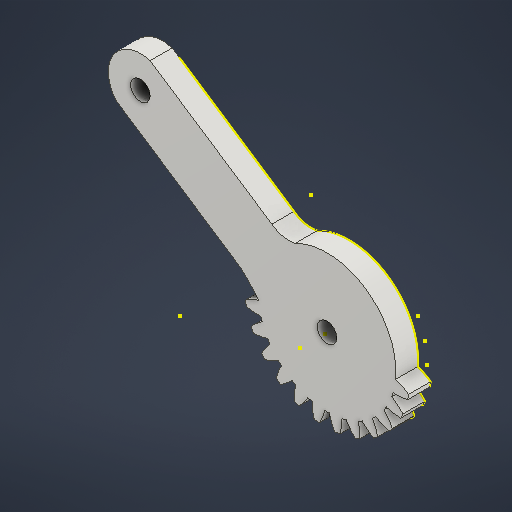
# Autodesk Inventor part: Przekładnia walcowa1
Saved by Autodesk Inventor 2026.1 (Build 301233020, 233B)
## iProperties
CustomPartVersion: 1
Created: 2026-01-25
Part Number: Przekładnia walcowa1
Material: Steel
Document SubType Name: Modeling
Designer: Nitro
Categories: <?xml version="1.0" encoding="UTF-16"?> <MemberInstance><Categories><FamilyTemplate><FamilyTemplateParameter ValueType="xs:double" Id="1" ObjectReferenceKey="da_z" ObjectType="kUserParameterObject"/><FamilyTemplateParameter ValueType="xs:double" Id="2" ObjectReferenceKey="da_b" ObjectType="kUserParameterObject"/><FamilyTemplateParameter ValueType="xs:double" Id="3" ObjectReferenceKey="da_beta" ObjectType="kUserParameterObject"/><FamilyTemplateParameter ValueType="xs:double" Id="4" ObjectReferenceKey="da_da" ObjectType="kUserParameterObject"/><FamilyTemplateParameter ValueType="xs:double" Id="5" ObjectReferenceKey="da_aw" ObjectType="kUserParameterObject"/><FamilyTemplateParameter ValueType="xs:string" Id="6" ObjectReferenceKey="EAIAABAAAACIAQAAAAAAAIAAAAAAAAAA" ObjectType="83910656" SubObjectId="SurfaceGeometry"/></FamilyTemplate><ParamToTemplateMap><ParamToTemplate CategoryParameter="//CategoryParameter[@InternalName='046C89C9-8512-4d59-83FE-43B91F4F132A']" TemplateParameter="1"/><ParamToTemplate CategoryParameter="//CategoryParameter[@InternalName='2552DF32-E462-4b46-AEBF-C6C7768E72AC']" TemplateParameter="2"/><ParamToTemplate CategoryParameter="//CategoryParameter[@InternalName='C9EE641D-15FC-4fae-A226-E94C4372FDD7']" TemplateParameter="3"/><ParamToTemplate><ParamToTemplate CategoryParameter="//CategoryParameter[@InternalName='00B6519A-459B-49c7-AD84-2E56D39A5744']" ConstantValue="0.000000"/></ParamToTemplate><ParamToTemplate><ParamToTemplate CategoryParameter="//CategoryParameter[@InternalName='04B31F0E-C7A6-4894-AA32-9629BEFACF47']" ConstantValue="1.000000"/></ParamToTemplate><ParamToTemplate><ParamToTemplate CategoryParameter="//CategoryParameter[@InternalName='43CBEC2E-7847-49e7-A936-2F7889FCB2D9']" ConstantValue="0.250000"/></ParamToTemplate><ParamToTemplate><ParamToTemplate CategoryParameter="//CategoryParameter[@InternalName='B1EFC894-105D-4ebd-86BF-FA20ED196853']" ConstantValue="0.350000"/></ParamToTemplate><ParamToTemplate><ParamToTemplate CategoryParameter="//CategoryParameter[@InternalName='51175063-3D10-4879-93E8-6246FE8B403D']" ConstantValue="2060000000.000000"/></ParamToTemplate><ParamToTemplate><ParamToTemplate CategoryParameter="//CategoryParameter[@InternalName='A3A52E27-4454-46a9-B0BD-C932399B70AF']" ConstantValue="0.300000"/></ParamToTemplate><ParamToTemplate><ParamToTemplate CategoryParameter="//CategoryParameter[@InternalName='91B76062-C214-41d9-B1B9-14D2AB99603D']" ConstantValue="0.125000"/></ParamToTemplate><ParamToTemplate><ParamToTemplate CategoryParameter="//CategoryParameter[@InternalName='374E806E-8B8A-4dda-A9AA-1039D6500AD2']" ConstantValue="8.000000"/></ParamToTemplate><ParamToTemplate><ParamToTemplate CategoryParameter="//CategoryParameter[@InternalName='2D373A89-B862-43d6-8D0B-0CBF12AB9F6C']" ConstantValue="0.349066"/></ParamToTemplate><ParamToTemplate CategoryParameter="//CategoryParameter[@InternalName='37777632-D6A2-4fac-9D53-DB8ACD95C989']" TemplateParameter="4"/><ParamToTemplate CategoryParameter="//CategoryParameter[@InternalName='FD1017F1-B727-4f7e-9707-0F86F1FF9423']" TemplateParameter="5"/><ParamToTemplate><ParamToTemplate CategoryParameter="//CategoryParameter[@InternalName='9E1B4470-B2D3-4ff1-B813-535BB4CDF51A']" ConstantValue="3520000.000000"/></ParamToTemplate><ParamToTemplate><ParamToTemplate CategoryParameter="//CategoryParameter[@InternalName='F8452263-BFF6-458c-9FB1-07C4B99E95CD']" ConstantValue="11400000.000000"/></ParamToTemplate><ParamToTemplate><ParamToTemplate CategoryParameter="//CategoryParameter[@InternalName='3E3BB259-FD49-497f-8171-6EBC954A3479']" ConstantValue="2.000000"/></ParamToTemplate><ParamToTemplate CategoryParameter="//CategoryParameter[@InternalName='27C3BAF2-7550-4e4b-AE2C-0DB134B7D9B7']" TemplateParameter="6"/></ParamToTemplateMap><Category DisplayName="Gear" InternalName="DC85795E-93AB-48d5-8EEE-5A27447B64BD" Mnemonic="Gear"><CategoryParameter DisplayName="z" InternalName="046C89C9-8512-4d59-83FE-43B91F4F132A" Mnemonic="z"/><CategoryParameter DisplayName="b" InternalName="2552DF32-E462-4b46-AEBF-C6C7768E72AC" Mnemonic="b"/><CategoryParameter DisplayName="||b|" InternalName="C9EE641D-15FC-4fae-A226-E94C4372FDD7" Mnemonic="beta"/><CategoryParameter DisplayName="x" InternalName="00B6519A-459B-49c7-AD84-2E56D39A5744" Mnemonic="x"/><CategoryParameter DisplayName="a*" InternalName="04B31F0E-C7A6-4894-AA32-9629BEFACF47" Mnemonic="a"/><CategoryParameter DisplayName="c*" InternalName="43CBEC2E-7847-49e7-A936-2F7889FCB2D9" Mnemonic="c"/><CategoryParameter DisplayName="r|.f|*" InternalName="B1EFC894-105D-4ebd-86BF-FA20ED196853" Mnemonic="rf"/><CategoryParameter DisplayName="E" InternalName="51175063-3D10-4879-93E8-6246FE8B403D" Mnemonic="E"/><CategoryParameter DisplayName="||m|" InternalName="A3A52E27-4454-46a9-B0BD-C932399B70AF" Mnemonic="mi"/><Category DisplayName="SpurGear" InternalName="26C5A22E-A91E-4dfd-A3B3-23CCAFAE1764" Mnemonic="SpurGear"><CategoryParameter DisplayName="m" InternalName="91B76062-C214-41d9-B1B9-14D2AB99603D" Mnemonic="m"/><CategoryParameter DisplayName="P" InternalName="374E806E-8B8A-4dda-A9AA-1039D6500AD2" Mnemonic="PP"/><CategoryParameter DisplayName="||a|" InternalName="2D373A89-B862-43d6-8D0B-0CBF12AB9F6C" Mnemonic="alpha"/><CategoryParameter DisplayName="d|.a|" InternalName="37777632-D6A2-4fac-9D53-DB8ACD95C989" Mnemonic="da"/><CategoryParameter DisplayName="a|.w|" InternalName="FD1017F1-B727-4f7e-9707-0F86F1FF9423" Mnemonic="aw"/><CategoryParameter DisplayName="||s||.Flim|" InternalName="9E1B4470-B2D3-4ff1-B813-535BB4CDF51A" Mnemonic="sFlim"/><CategoryParameter DisplayName="||s||.Hlim|" InternalName="F8452263-BFF6-458c-9FB1-07C4B99E95CD" Mnemonic="sHlim"/><CategoryParameter DisplayName="typ" InternalName="3E3BB259-FD49-497f-8171-6EBC954A3479" Mnemonic="type"/><CategoryParameter DisplayName="PitchDiameter" InternalName="27C3BAF2-7550-4e4b-AE2C-0DB134B7D9B7" Mnemonic="IDS_PITCHDIAM"/></Category></Category></Categories></MemberInstance>
Density: 1 g/cm^3
Appearance: Steel
Description: Zebatki chwytaka
Author: Nitro
Autodesk Inventor part; units mm, degrees
sketch "Sketch1" plane through (0, 0, 0) normal (0, 0, 1) x (1, 0, 0)
  circle A0 centre (0, 0) radius 16.875
  dimension "d0" = 33.75
  constraints: 1 centre point
  measures "d0" diameter of A0
extrude "Extrusion1" add sketch "Sketch1" along normal blind 10
ref_plane "Work Plane2" through (0, 0, 5) normal (0, 0, 1) x (1, 0, 0)
sketch "Sketch2" plane through (0, 0, 0) normal (0, 0, -1) x (-1, 0, 0)
  circle A0 centre (0, 0) radius 16.875 projected
  circle A1 centre (0, 0) radius 15.625
  dimension "d3" = 31.25
  constraints: 1 centre point, 1 coincident
  measures "d3" diameter of A1
surface extrude "Średnica podziałowa" sketch "Sketch2" against normal through all shown no curves A1
ref_plane "Work Plane8" through (0, 0, 0) normal (0.9921147, 0.1253332, 0) x (0, 0, 1)
ref_plane "Work Plane9" through (0, 0, 0) normal (1, 0, 0) x (0, 1, 0)
spur gear teeth "Przekładnia walcowa" teeth 25 pitch diameter 31.25 tip diameter 33.75 root diameter 28.125 face width 10 start plane through (0, 0, 0) normal (0, 0, -1) x (-1, 0, 0)
sketch "Szkic3" plane through (0, 0, 10) normal (0, 0, 1) x (1, 0, 0)
  point P0 (0, 0)
sketch "Szkic4" plane through (0, 0, 10) normal (0, 0, 1) x (1, 0, 0)
  circle A0 centre (0, 0) radius 14.0625
  circle A1 centre (0, 0) radius 17.8459
  line L0 (-14.0332, -0.9078) -> (-17.7928, -1.3752)
  line L1 (14.0556, -0.9078) -> (17.7928, -1.3752)
  arc A2 (-4.708, 16.205) -> (-4.7635, 13.2311) centre (6.716, 14.5042) ccw projected
  arc A3 (-4.7635, 13.2311) -> (-5.5849, 12.9059) centre (0, 0) ccw projected
  arc A4 (-5.5849, 12.9059) -> (-7.6611, 15.0357) centre (-14.8245, 5.9757) ccw projected
  arc A5 (-7.6611, 15.0357) -> (-8.5901, 14.525) centre (0, 0) ccw projected
  arc A6 (-8.5901, 14.525) -> (-7.9043, 11.6308) centre (2.8979, 15.7187) ccw projected
  arc A7 (-7.9043, 11.6308) -> (-8.619, 11.1116) centre (0, 0) ccw projected
  arc A8 (-8.619, 11.1116) -> (-11.1596, 12.6581) centre (-15.8449, 2.1013) ccw projected
  arc A9 (-11.1596, 12.6581) -> (-11.9324, 11.9324) centre (0, 0) ccw projected
  arc A10 (-11.9324, 11.9324) -> (-10.5484, 9.2997) centre (-1.1022, 15.9456) ccw projected
  arc A11 (-10.5484, 9.2997) -> (-11.1116, 8.619) centre (0, 0) ccw projected
  arc A12 (-11.1116, 8.619) -> (-13.957, 9.4852) centre (-15.8697, -1.9052) ccw projected
  arc A13 (-13.957, 9.4852) -> (-14.525, 8.5901) centre (0, 0) ccw projected
  arc A14 (-14.525, 8.5901) -> (-12.5298, 6.3842) centre (-5.0331, 15.1705) ccw projected
  arc A15 (-12.5298, 6.3842) -> (-12.9059, 5.5849) centre (0, 0) ccw projected
  arc A16 (-12.9059, 5.5849) -> (-15.8774, 5.7162) centre (-14.8973, -5.792) ccw projected
  arc A17 (-15.8774, 5.7162) -> (-16.205, 4.708) centre (0, 0) ccw projected
  arc A18 (-16.205, 4.708) -> (-13.7238, 3.0676) centre (-8.6477, 13.4422) ccw projected
  arc A19 (-13.7238, 3.0676) -> (-13.8894, 2.1999) centre (0, 0) ccw projected
  arc A20 (-13.8894, 2.1999) -> (-16.8001, 1.5881) centre (-12.9889, -9.3148) ccw projected
  arc A21 (-16.8001, 1.5881) -> (-16.8667, 0.5301) centre (0, 0) ccw projected
  arc A22 (-16.8667, 0.5301) -> (-14.0556, -0.4417) centre (-11.719, 10.8693) ccw projected
  arc A23 (-14.0556, -0.4417) -> (-14.0001, -1.3234) centre (0, 0) ccw projected
  arc A24 (-14.0001, -1.3234) -> (-16.6672, -2.6398) centre (-10.2643, -12.2524) ccw projected
  arc A25 (-16.6672, -2.6398) -> (-16.4686, -3.6812) centre (0, 0) ccw projected
  arc A26 (-16.4686, -3.6812) -> (-13.5041, -3.9233) centre (-14.0539, 7.6134) ccw projected
  arc A27 (-13.5041, -3.9233) -> (-13.2311, -4.7635) centre (0, 0) ccw projected
  arc A28 (-13.2311, -4.7635) -> (-15.4871, -6.7019) centre (-6.8948, -14.4201) ccw projected
  arc A29 (-15.4871, -6.7019) -> (-15.0357, -7.6611) centre (0, 0) ccw projected
  arc A30 (-15.0357, -7.6611) -> (-12.1042, -7.1584) centre (-15.5058, 3.8792) ccw projected
  arc A31 (-12.1042, -7.1584) -> (-11.6308, -7.9043) centre (0, 0) ccw projected
  arc A32 (-11.6308, -7.9043) -> (-13.3339, -10.3428) centre (-3.092, -15.6817) ccw projected
  arc A33 (-13.3339, -10.3428) -> (-12.6581, -11.1596) centre (0, 0) ccw projected
  arc A34 (-12.6581, -11.1596) -> (-9.9437, -9.9437) centre (-15.9833, -0.0988) ccw projected
  arc A35 (-9.9437, -9.9437) -> (-9.2997, -10.5484) centre (0, 0) ccw projected
  arc A36 (-9.2997, -10.5484) -> (-10.3428, -13.3339) centre (0.905, -15.958) ccw projected
  arc A37 (-10.3428, -13.3339) -> (-9.4852, -13.957) centre (0, 0) ccw projected
  arc A38 (-9.4852, -13.957) -> (-7.1584, -12.1042) centre (-15.4566, -4.0706) ccw projected
  arc A39 (-7.1584, -12.1042) -> (-6.3842, -12.5298) centre (0, 0) ccw projected
  arc A40 (-6.3842, -12.5298) -> (-6.7019, -15.4871) centre (4.8451, -15.2316) ccw projected
  arc A41 (-6.7019, -15.4871) -> (-5.7162, -15.8774) centre (0, 0) ccw projected
  arc A42 (-5.7162, -15.8774) -> (-3.9233, -13.5041) centre (-13.9587, -7.7866) ccw projected
  arc A43 (-3.9233, -13.5041) -> (-3.0676, -13.7238) centre (0, 0) ccw projected
  arc A44 (-3.0676, -13.7238) -> (-2.6398, -16.6672) centre (8.4809, -13.5481) ccw projected
  arc A45 (-2.6398, -16.6672) -> (-1.5881, -16.8001) centre (0, 0) ccw projected
  arc A46 (-1.5881, -16.8001) -> (-0.4417, -14.0556) centre (-11.5837, -11.0134) ccw projected
  arc A47 (-0.4417, -14.0556) -> (0.4417, -14.0556) centre (0, 0) ccw projected
  arc A48 (0.4417, -14.0556) -> (1.5881, -16.8001) centre (11.5837, -11.0134) ccw projected
  arc A49 (1.5881, -16.8001) -> (2.6398, -16.6672) centre (0, 0) ccw projected
  arc A50 (2.6398, -16.6672) -> (3.0676, -13.7238) centre (-8.4809, -13.5481) ccw projected
  arc A51 (3.0676, -13.7238) -> (3.9233, -13.5041) centre (0, 0) ccw projected
  arc A52 (3.9233, -13.5041) -> (5.7162, -15.8774) centre (13.9587, -7.7866) ccw projected
  arc A53 (5.7162, -15.8774) -> (6.7019, -15.4871) centre (0, 0) ccw projected
  arc A54 (6.7019, -15.4871) -> (6.3842, -12.5298) centre (-4.8451, -15.2316) ccw projected
  arc A55 (6.3842, -12.5298) -> (7.1584, -12.1042) centre (0, 0) ccw projected
  arc A56 (7.1584, -12.1042) -> (9.4852, -13.957) centre (15.4566, -4.0706) ccw projected
  arc A57 (9.4852, -13.957) -> (10.3428, -13.3339) centre (0, 0) ccw projected
  arc A58 (10.3428, -13.3339) -> (9.2997, -10.5484) centre (-0.905, -15.958) ccw projected
  arc A59 (9.2997, -10.5484) -> (9.9437, -9.9437) centre (0, 0) ccw projected
  arc A60 (9.9437, -9.9437) -> (12.6581, -11.1596) centre (15.9833, -0.0988) ccw projected
  arc A61 (12.6581, -11.1596) -> (13.3339, -10.3428) centre (0, 0) ccw projected
  arc A62 (13.3339, -10.3428) -> (11.6308, -7.9043) centre (3.092, -15.6817) ccw projected
  arc A63 (11.6308, -7.9043) -> (12.1042, -7.1584) centre (0, 0) ccw projected
  arc A64 (12.1042, -7.1584) -> (15.0357, -7.6611) centre (15.5058, 3.8792) ccw projected
  arc A65 (15.0357, -7.6611) -> (15.4871, -6.7019) centre (0, 0) ccw projected
  arc A66 (15.4871, -6.7019) -> (13.2311, -4.7635) centre (6.8948, -14.4201) ccw projected
  arc A67 (13.2311, -4.7635) -> (13.5041, -3.9233) centre (0, 0) ccw projected
  arc A68 (13.5041, -3.9233) -> (16.4686, -3.6812) centre (14.0539, 7.6134) ccw projected
  arc A69 (16.4686, -3.6812) -> (16.6672, -2.6398) centre (0, 0) ccw projected
  arc A70 (16.6672, -2.6398) -> (14.0001, -1.3234) centre (10.2643, -12.2524) ccw projected
  arc A71 (14.0001, -1.3234) -> (14.0556, -0.4417) centre (0, 0) ccw projected
  arc A72 (14.0556, -0.4417) -> (16.8667, 0.5301) centre (11.719, 10.8693) ccw projected
  arc A73 (16.8667, 0.5301) -> (16.8001, 1.5881) centre (0, 0) ccw projected
  arc A74 (16.8001, 1.5881) -> (13.8894, 2.1999) centre (12.9889, -9.3148) ccw projected
  arc A75 (13.8894, 2.1999) -> (13.7238, 3.0676) centre (0, 0) ccw projected
  arc A76 (13.7238, 3.0676) -> (16.205, 4.708) centre (8.6477, 13.4422) ccw projected
  arc A77 (16.205, 4.708) -> (15.8774, 5.7162) centre (0, 0) ccw projected
  arc A78 (15.8774, 5.7162) -> (12.9059, 5.5849) centre (14.8973, -5.792) ccw projected
  arc A79 (12.9059, 5.5849) -> (12.5298, 6.3842) centre (0, 0) ccw projected
  arc A80 (12.5298, 6.3842) -> (14.525, 8.5901) centre (5.0331, 15.1705) ccw projected
  arc A81 (14.525, 8.5901) -> (13.957, 9.4852) centre (0, 0) ccw projected
  arc A82 (13.957, 9.4852) -> (11.1116, 8.619) centre (15.8697, -1.9052) ccw projected
  arc A83 (11.1116, 8.619) -> (10.5484, 9.2997) centre (0, 0) ccw projected
  arc A84 (10.5484, 9.2997) -> (11.9324, 11.9324) centre (1.1022, 15.9456) ccw projected
  arc A85 (11.9324, 11.9324) -> (11.1596, 12.6581) centre (0, 0) ccw projected
  arc A86 (11.1596, 12.6581) -> (8.619, 11.1116) centre (15.8449, 2.1013) ccw projected
  arc A87 (8.619, 11.1116) -> (7.9043, 11.6308) centre (0, 0) ccw projected
  arc A88 (7.9043, 11.6308) -> (8.5901, 14.525) centre (-2.8979, 15.7187) ccw projected
  arc A89 (8.5901, 14.525) -> (7.6611, 15.0357) centre (0, 0) ccw projected
  arc A90 (7.6611, 15.0357) -> (5.5849, 12.9059) centre (14.8245, 5.9757) ccw projected
  arc A91 (5.5849, 12.9059) -> (4.7635, 13.2311) centre (0, 0) ccw projected
  arc A92 (4.7635, 13.2311) -> (4.708, 16.205) centre (-6.716, 14.5042) ccw projected
  arc A93 (4.708, 16.205) -> (3.6812, 16.4686) centre (0, 0) ccw projected
  arc A94 (3.6812, 16.4686) -> (2.1999, 13.8894) centre (12.8727, 9.4747) ccw projected
  arc A95 (2.1999, 13.8894) -> (1.3234, 14.0001) centre (0, 0) ccw projected
  arc A96 (1.3234, 14.0001) -> (0.5301, 16.8667) centre (-10.112, 12.3784) ccw projected
  arc A97 (0.5301, 16.8667) -> (-0.5301, 16.8667) centre (0, 0) ccw projected
  arc A98 (-0.5301, 16.8667) -> (-1.3234, 14.0001) centre (10.112, 12.3784) ccw projected
  arc A99 (-1.3234, 14.0001) -> (-2.1999, 13.8894) centre (0, 0) ccw projected
  arc A100 (-2.1999, 13.8894) -> (-3.6812, 16.4686) centre (-12.8727, 9.4747) ccw projected
  arc A101 (-3.6812, 16.4686) -> (-4.708, 16.205) centre (0, 0) ccw projected
  point P0 (14.0001, -1.3234)
  point P1 (13.5041, -3.9233)
  point P2 (13.2311, -4.7635)
  point P3 (12.1042, -7.1584)
  point P4 (11.6308, -7.9043)
  point P5 (9.9437, -9.9437)
  point P6 (9.2997, -10.5484)
  point P7 (7.1584, -12.1042)
  point P8 (6.3842, -12.5298)
  point P9 (3.9233, -13.5041)
  point P10 (3.0676, -13.7238)
  point P11 (0.4417, -14.0556)
  point P12 (-0.4417, -14.0556)
  point P13 (-3.0676, -13.7238)
  point P14 (-3.9233, -13.5041)
  point P15 (-6.3842, -12.5298)
  point P16 (-7.1584, -12.1042)
  point P17 (-9.2997, -10.5484)
  point P18 (-9.9437, -9.9437)
  point P19 (-11.6308, -7.9043)
  point P20 (-12.1042, -7.1584)
  point P21 (-13.2311, -4.7635)
  point P22 (-13.5041, -3.9233)
  point P23 (-14.0001, -1.3234)
  constraints: 4 end point, 2 coincident, 2 point on circle, 1 centre point, 4 other
extrude "Wyciągnięcie proste2" cut sketch "Szkic4" against normal blind 10 contours A0 A74 A73 A72 | A0 A78 A77 A76 | A0 A82 A81 A80 | A0 A86 A85 A84 | A0 A90 A89 A88 | A0 A94 A93 A92 | A0 A98 A97 A96 | A0 A2 A101 A100 | A0 A6 A5 A4 | A0 A10 A9 A8 | A0 A14 A13 A12 | A0 A18 A17 A16 | A0 A22 A21 A20 | A1
sketch "Szkic5" plane through (0, 0, 10) normal (0, 0, 1) x (1, 0, 0)
  circle A0 centre (0, 0) radius 25.2882
  constraints: 1 centre point, 1 coincident
extrude "Wyciągnięcie proste3" cut sketch "Szkic5" against normal blind 5
sketch "Szkic6" plane through (0, 0, 5) normal (0, 0, 1) x (1, 0, 0)
  point P0 (0, 0)
sketch "Szkic7" plane through (0, 0, 5) normal (0, 0, 1) x (1, 0, 0)
  point P0 (0, 0)
sketch "Szkic8" plane through (0, 0, 5) normal (0, 0, 1) x (1, 0, 0)
  arc A0 (13.2311, -4.7635) -> (13.5041, -3.9233) centre (0, 0) ccw projected
  arc A1 (13.5041, -3.9233) -> (16.4686, -3.6812) centre (14.0539, 7.6134) ccw projected
  arc A2 (16.4686, -3.6812) -> (16.6672, -2.6398) centre (0, 0) ccw projected
  arc A3 (16.6672, -2.6398) -> (14.0001, -1.3234) centre (10.2643, -12.2524) ccw projected
  arc A4 (14.0001, -1.3234) -> (-14.0001, -1.3234) centre (0, 0) ccw projected
  arc A5 (-14.0001, -1.3234) -> (-16.6672, -2.6398) centre (-10.2643, -12.2524) ccw projected
  arc A6 (-16.6672, -2.6398) -> (-16.4686, -3.6812) centre (0, 0) ccw projected
  arc A7 (-16.4686, -3.6812) -> (-13.5041, -3.9233) centre (-14.0539, 7.6134) ccw projected
  arc A8 (-13.5041, -3.9233) -> (-13.2311, -4.7635) centre (0, 0) ccw projected
  arc A9 (-13.2311, -4.7635) -> (-15.4871, -6.7019) centre (-6.8948, -14.4201) ccw projected
  arc A10 (-15.4871, -6.7019) -> (-15.0357, -7.6611) centre (0, 0) ccw projected
  arc A11 (-15.0357, -7.6611) -> (-12.1042, -7.1584) centre (-15.5058, 3.8792) ccw projected
  arc A12 (-12.1042, -7.1584) -> (-11.6308, -7.9043) centre (0, 0) ccw projected
  arc A13 (-11.6308, -7.9043) -> (-13.3339, -10.3428) centre (-3.092, -15.6817) ccw projected
  arc A14 (-13.3339, -10.3428) -> (-12.6581, -11.1596) centre (0, 0) ccw projected
  arc A15 (-12.6581, -11.1596) -> (-9.9437, -9.9437) centre (-15.9833, -0.0988) ccw projected
  arc A16 (-9.9437, -9.9437) -> (-9.2997, -10.5484) centre (0, 0) ccw projected
  arc A17 (-9.2997, -10.5484) -> (-10.3428, -13.3339) centre (0.905, -15.958) ccw projected
  arc A18 (-10.3428, -13.3339) -> (-9.4852, -13.957) centre (0, 0) ccw projected
  arc A19 (-9.4852, -13.957) -> (-7.1584, -12.1042) centre (-15.4566, -4.0706) ccw projected
  arc A20 (-7.1584, -12.1042) -> (-6.3842, -12.5298) centre (0, 0) ccw projected
  arc A21 (-6.3842, -12.5298) -> (-6.7019, -15.4871) centre (4.8451, -15.2316) ccw projected
  arc A22 (-6.7019, -15.4871) -> (-5.7162, -15.8774) centre (0, 0) ccw projected
  arc A23 (-5.7162, -15.8774) -> (-3.9233, -13.5041) centre (-13.9587, -7.7866) ccw projected
  arc A24 (-3.9233, -13.5041) -> (-3.0676, -13.7238) centre (0, 0) ccw projected
  arc A25 (-3.0676, -13.7238) -> (-2.6398, -16.6672) centre (8.4809, -13.5481) ccw projected
  arc A26 (-2.6398, -16.6672) -> (-1.5881, -16.8001) centre (0, 0) ccw projected
  arc A27 (-1.5881, -16.8001) -> (-0.4417, -14.0556) centre (-11.5837, -11.0134) ccw projected
  arc A28 (-0.4417, -14.0556) -> (0.4417, -14.0556) centre (0, 0) ccw projected
  arc A29 (0.4417, -14.0556) -> (1.5881, -16.8001) centre (11.5837, -11.0134) ccw projected
  arc A30 (1.5881, -16.8001) -> (2.6398, -16.6672) centre (0, 0) ccw projected
  arc A31 (2.6398, -16.6672) -> (3.0676, -13.7238) centre (-8.4809, -13.5481) ccw projected
  arc A32 (3.0676, -13.7238) -> (3.9233, -13.5041) centre (0, 0) ccw projected
  arc A33 (3.9233, -13.5041) -> (5.7162, -15.8774) centre (13.9587, -7.7866) ccw projected
  arc A34 (5.7162, -15.8774) -> (6.7019, -15.4871) centre (0, 0) ccw projected
  arc A35 (6.7019, -15.4871) -> (6.3842, -12.5298) centre (-4.8451, -15.2316) ccw projected
  arc A36 (6.3842, -12.5298) -> (7.1584, -12.1042) centre (0, 0) ccw projected
  arc A37 (7.1584, -12.1042) -> (9.4852, -13.957) centre (15.4566, -4.0706) ccw projected
  arc A38 (9.4852, -13.957) -> (10.3428, -13.3339) centre (0, 0) ccw projected
  arc A39 (10.3428, -13.3339) -> (9.2997, -10.5484) centre (-0.905, -15.958) ccw projected
  arc A40 (9.2997, -10.5484) -> (9.9437, -9.9437) centre (0, 0) ccw projected
  arc A41 (9.9437, -9.9437) -> (12.6581, -11.1596) centre (15.9833, -0.0988) ccw projected
  arc A42 (12.6581, -11.1596) -> (13.3339, -10.3428) centre (0, 0) ccw projected
  arc A43 (13.3339, -10.3428) -> (11.6308, -7.9043) centre (3.092, -15.6817) ccw projected
  arc A44 (11.6308, -7.9043) -> (12.1042, -7.1584) centre (0, 0) ccw projected
  arc A45 (12.1042, -7.1584) -> (15.0357, -7.6611) centre (15.5058, 3.8792) ccw projected
  arc A46 (15.0357, -7.6611) -> (15.4871, -6.7019) centre (0, 0) ccw projected
  arc A47 (15.4871, -6.7019) -> (13.2311, -4.7635) centre (6.8948, -14.4201) ccw projected
  line L0 (-8.1721, 11.4442) -> (-34.5152, 28.8945)
  line L1 (-14.0607, 0.2225) -> (-41.4775, 18.3841)
  line L2 (-5.8927, 15.7879) -> (-5.8933, 15.7868)
  arc A48 (-34.5152, 28.8945) -> (-41.4775, 18.3841) centre (-36.4521, 22.6163) ccw
  arc A49 (-11.2616, 13.4908) -> (-6.5061, 12.4669) centre (-7.7853, 18.0815) ccw
  line L3 (-10.6564, 13.0899) -> (-17.6188, 2.5795)
  arc A50 (14.0001, -1.3234) -> (-14.0001, -1.3234) centre (0, 0) ccw projected
  arc A51 (-14.0001, -1.3234) -> (-17.6188, 2.5795) centre (-34.4614, -16.666) ccw
  constraints: 11 point on circle, 8 end point, 4 point on line, 3 centre point, 2 coincident, 1 parallel, 1 perpendicular
extrude "Wyciągnięcie proste4" add sketch "Szkic8" against normal blind 5 contours A4 L0 A49 | A4 L1 L3 L0 | L3 L1 A48 L0 A49 | A4 A51 L1
sketch "Szkic9" plane through (0, 0, 5) normal (0, 0, 1) x (1, 0, 0)
  arc A0 (13.2311, -4.7635) -> (13.5041, -3.9233) centre (0, 0) ccw projected
  arc A1 (13.5041, -3.9233) -> (16.4686, -3.6812) centre (14.0539, 7.6134) ccw projected
  arc A2 (16.4686, -3.6812) -> (16.6672, -2.6398) centre (0, 0) ccw projected
  arc A3 (16.6672, -2.6398) -> (14.0001, -1.3234) centre (10.2643, -12.2524) ccw projected
  arc A4 (14.0001, -1.3234) -> (-6.5061, 12.4669) centre (0, 0) ccw projected
  arc A5 (-11.2616, 13.4908) -> (-6.5061, 12.4669) centre (-7.7853, 18.0815) ccw projected
  line L0 (-11.2616, 13.4908) -> (-34.5152, 28.8945) projected
  arc A6 (-34.5152, 28.8945) -> (-41.4775, 18.3841) centre (-36.4521, 22.6163) ccw projected
  line L1 (-41.4775, 18.3841) -> (-17.6188, 2.5795) projected
  arc A7 (-14.0001, -1.3234) -> (-17.6188, 2.5795) centre (-34.4614, -16.666) ccw projected
  arc A8 (-14.0001, -1.3234) -> (-16.6672, -2.6398) centre (-10.2643, -12.2524) ccw projected
  arc A9 (-16.6672, -2.6398) -> (-16.4686, -3.6812) centre (0, 0) ccw projected
  arc A10 (-16.4686, -3.6812) -> (-13.5041, -3.9233) centre (-14.0539, 7.6134) ccw projected
  arc A11 (-13.5041, -3.9233) -> (-13.2311, -4.7635) centre (0, 0) ccw projected
  arc A12 (-13.2311, -4.7635) -> (-15.4871, -6.7019) centre (-6.8948, -14.4201) ccw projected
  arc A13 (-15.4871, -6.7019) -> (-15.0357, -7.6611) centre (0, 0) ccw projected
  arc A14 (-15.0357, -7.6611) -> (-12.1042, -7.1584) centre (-15.5058, 3.8792) ccw projected
  arc A15 (-12.1042, -7.1584) -> (-11.6308, -7.9043) centre (0, 0) ccw projected
  arc A16 (-11.6308, -7.9043) -> (-13.3339, -10.3428) centre (-3.092, -15.6817) ccw projected
  arc A17 (-13.3339, -10.3428) -> (-12.6581, -11.1596) centre (0, 0) ccw projected
  arc A18 (-12.6581, -11.1596) -> (-9.9437, -9.9437) centre (-15.9833, -0.0988) ccw projected
  arc A19 (-9.9437, -9.9437) -> (-9.2997, -10.5484) centre (0, 0) ccw projected
  arc A20 (-9.2997, -10.5484) -> (-10.3428, -13.3339) centre (0.905, -15.958) ccw projected
  arc A21 (-10.3428, -13.3339) -> (-9.4852, -13.957) centre (0, 0) ccw projected
  arc A22 (-9.4852, -13.957) -> (-7.1584, -12.1042) centre (-15.4566, -4.0706) ccw projected
  arc A23 (-7.1584, -12.1042) -> (-6.3842, -12.5298) centre (0, 0) ccw projected
  arc A24 (-6.3842, -12.5298) -> (-6.7019, -15.4871) centre (4.8451, -15.2316) ccw projected
  arc A25 (-6.7019, -15.4871) -> (-5.7162, -15.8774) centre (0, 0) ccw projected
  arc A26 (-5.7162, -15.8774) -> (-3.9233, -13.5041) centre (-13.9587, -7.7866) ccw projected
  arc A27 (-3.9233, -13.5041) -> (-3.0676, -13.7238) centre (0, 0) ccw projected
  arc A28 (-3.0676, -13.7238) -> (-2.6398, -16.6672) centre (8.4809, -13.5481) ccw projected
  arc A29 (-2.6398, -16.6672) -> (-1.5881, -16.8001) centre (0, 0) ccw projected
  arc A30 (-1.5881, -16.8001) -> (-0.4417, -14.0556) centre (-11.5837, -11.0134) ccw projected
  arc A31 (-0.4417, -14.0556) -> (0.4417, -14.0556) centre (0, 0) ccw projected
  arc A32 (0.4417, -14.0556) -> (1.5881, -16.8001) centre (11.5837, -11.0134) ccw projected
  arc A33 (1.5881, -16.8001) -> (2.6398, -16.6672) centre (0, 0) ccw projected
  arc A34 (2.6398, -16.6672) -> (3.0676, -13.7238) centre (-8.4809, -13.5481) ccw projected
  arc A35 (3.0676, -13.7238) -> (3.9233, -13.5041) centre (0, 0) ccw projected
  arc A36 (3.9233, -13.5041) -> (5.7162, -15.8774) centre (13.9587, -7.7866) ccw projected
  arc A37 (5.7162, -15.8774) -> (6.7019, -15.4871) centre (0, 0) ccw projected
  arc A38 (6.7019, -15.4871) -> (6.3842, -12.5298) centre (-4.8451, -15.2316) ccw projected
  arc A39 (6.3842, -12.5298) -> (7.1584, -12.1042) centre (0, 0) ccw projected
  arc A40 (7.1584, -12.1042) -> (9.4852, -13.957) centre (15.4566, -4.0706) ccw projected
  arc A41 (9.4852, -13.957) -> (10.3428, -13.3339) centre (0, 0) ccw projected
  arc A42 (10.3428, -13.3339) -> (9.2997, -10.5484) centre (-0.905, -15.958) ccw projected
  arc A43 (9.2997, -10.5484) -> (9.9437, -9.9437) centre (0, 0) ccw projected
  arc A44 (9.9437, -9.9437) -> (12.6581, -11.1596) centre (15.9833, -0.0988) ccw projected
  arc A45 (12.6581, -11.1596) -> (13.3339, -10.3428) centre (0, 0) ccw projected
  arc A46 (13.3339, -10.3428) -> (11.6308, -7.9043) centre (3.092, -15.6817) ccw projected
  arc A47 (11.6308, -7.9043) -> (12.1042, -7.1584) centre (0, 0) ccw projected
  arc A48 (12.1042, -7.1584) -> (15.0357, -7.6611) centre (15.5058, 3.8792) ccw projected
  arc A49 (15.0357, -7.6611) -> (15.4871, -6.7019) centre (0, 0) ccw projected
  arc A50 (15.4871, -6.7019) -> (13.2311, -4.7635) centre (6.8948, -14.4201) ccw projected
  circle A51 centre (-36.4521, 22.6163) radius 3
  dimension "d55" = 6
  constraints: 1 centre point, 1 coincident
  measures "d55" diameter of A51
extrude "Wyciągnięcie proste5" cut sketch "Szkic9" against normal blind 5 contours A51
sketch "Szkic10" plane through (0, 0, 0) normal (0, 0, -1) x (-1, 0, 0)
  circle A0 centre (0, 0) radius 3
  dimension "d58" = 6
  constraints: 1 centre point, 1 coincident
  measures "d58" diameter of A0
extrude "Wyciągnięcie proste6" cut sketch "Szkic10" against normal blind 5
sketch "Szkic11" plane through (0, 0, 0) normal (0, 0, -1) x (-1, 0, 0)
  circle A0 centre (0, 0) radius 3 projected
  circle A1 centre (36.4521, 22.6163) radius 3 projected
  arc A2 (6.5061, 12.4669) -> (-14.0001, -1.3234) centre (0, 0) ccw projected
  arc A3 (-14.0001, -1.3234) -> (-16.6672, -2.6398) centre (-10.2643, -12.2524) ccw projected
  arc A4 (-16.6672, -2.6398) -> (-16.4686, -3.6812) centre (0, 0) ccw projected
  arc A5 (-16.4686, -3.6812) -> (-13.5041, -3.9233) centre (-14.0539, 7.6134) ccw projected
  arc A6 (-13.5041, -3.9233) -> (-13.2311, -4.7635) centre (0, 0) ccw projected
  arc A7 (-13.2311, -4.7635) -> (-15.4871, -6.7019) centre (-6.8948, -14.4201) ccw projected
  arc A8 (-15.4871, -6.7019) -> (-15.0357, -7.6611) centre (0, 0) ccw projected
  arc A9 (-15.0357, -7.6611) -> (-12.1042, -7.1584) centre (-15.5058, 3.8792) ccw projected
  arc A10 (-12.1042, -7.1584) -> (-11.6308, -7.9043) centre (0, 0) ccw projected
  arc A11 (-11.6308, -7.9043) -> (-13.3339, -10.3428) centre (-3.092, -15.6817) ccw projected
  arc A12 (-13.3339, -10.3428) -> (-12.6581, -11.1596) centre (0, 0) ccw projected
  arc A13 (-12.6581, -11.1596) -> (-9.9437, -9.9437) centre (-15.9833, -0.0988) ccw projected
  arc A14 (-9.9437, -9.9437) -> (-9.2997, -10.5484) centre (0, 0) ccw projected
  arc A15 (-9.2997, -10.5484) -> (-10.3428, -13.3339) centre (0.905, -15.958) ccw projected
  arc A16 (-10.3428, -13.3339) -> (-9.4852, -13.957) centre (0, 0) ccw projected
  arc A17 (-9.4852, -13.957) -> (-7.1584, -12.1042) centre (-15.4566, -4.0706) ccw projected
  arc A18 (-7.1584, -12.1042) -> (-6.3842, -12.5298) centre (0, 0) ccw projected
  arc A19 (-6.3842, -12.5298) -> (-6.7019, -15.4871) centre (4.8451, -15.2316) ccw projected
  arc A20 (-6.7019, -15.4871) -> (-5.7162, -15.8774) centre (0, 0) ccw projected
  arc A21 (-5.7162, -15.8774) -> (-3.9233, -13.5041) centre (-13.9587, -7.7866) ccw projected
  arc A22 (-3.9233, -13.5041) -> (-3.0676, -13.7238) centre (0, 0) ccw projected
  arc A23 (-3.0676, -13.7238) -> (-2.6398, -16.6672) centre (8.4809, -13.5481) ccw projected
  arc A24 (-2.6398, -16.6672) -> (-1.5881, -16.8001) centre (0, 0) ccw projected
  arc A25 (-1.5881, -16.8001) -> (-0.4417, -14.0556) centre (-11.5837, -11.0134) ccw projected
  arc A26 (-0.4417, -14.0556) -> (0.4417, -14.0556) centre (0, 0) ccw projected
  arc A27 (0.4417, -14.0556) -> (1.5881, -16.8001) centre (11.5837, -11.0134) ccw projected
  arc A28 (1.5881, -16.8001) -> (2.6398, -16.6672) centre (0, 0) ccw projected
  arc A29 (2.6398, -16.6672) -> (3.0676, -13.7238) centre (-8.4809, -13.5481) ccw projected
  arc A30 (3.0676, -13.7238) -> (3.9233, -13.5041) centre (0, 0) ccw projected
  arc A31 (3.9233, -13.5041) -> (5.7162, -15.8774) centre (13.9587, -7.7866) ccw projected
  arc A32 (5.7162, -15.8774) -> (6.7019, -15.4871) centre (0, 0) ccw projected
  arc A33 (6.7019, -15.4871) -> (6.3842, -12.5298) centre (-4.8451, -15.2316) ccw projected
  arc A34 (6.3842, -12.5298) -> (7.1584, -12.1042) centre (0, 0) ccw projected
  arc A35 (7.1584, -12.1042) -> (9.4852, -13.957) centre (15.4566, -4.0706) ccw projected
  arc A36 (9.4852, -13.957) -> (10.3428, -13.3339) centre (0, 0) ccw projected
  arc A37 (10.3428, -13.3339) -> (9.2997, -10.5484) centre (-0.905, -15.958) ccw projected
  arc A38 (9.2997, -10.5484) -> (9.9437, -9.9437) centre (0, 0) ccw projected
  arc A39 (9.9437, -9.9437) -> (12.6581, -11.1596) centre (15.9833, -0.0988) ccw projected
  arc A40 (12.6581, -11.1596) -> (13.3339, -10.3428) centre (0, 0) ccw projected
  arc A41 (13.3339, -10.3428) -> (11.6308, -7.9043) centre (3.092, -15.6817) ccw projected
  arc A42 (11.6308, -7.9043) -> (12.1042, -7.1584) centre (0, 0) ccw projected
  arc A43 (12.1042, -7.1584) -> (15.0357, -7.6611) centre (15.5058, 3.8792) ccw projected
  arc A44 (15.0357, -7.6611) -> (15.4871, -6.7019) centre (0, 0) ccw projected
  arc A45 (15.4871, -6.7019) -> (13.2311, -4.7635) centre (6.8948, -14.4201) ccw projected
  arc A46 (13.2311, -4.7635) -> (13.5041, -3.9233) centre (0, 0) ccw projected
  arc A47 (13.5041, -3.9233) -> (16.4686, -3.6812) centre (14.0539, 7.6134) ccw projected
  arc A48 (16.4686, -3.6812) -> (16.6672, -2.6398) centre (0, 0) ccw projected
  arc A49 (16.6672, -2.6398) -> (14.0001, -1.3234) centre (10.2643, -12.2524) ccw projected
  arc A50 (17.6188, 2.5795) -> (14.0001, -1.3234) centre (34.4614, -16.666) ccw projected
  line L0 (17.6188, 2.5795) -> (41.4775, 18.3841) projected
  arc A51 (41.4775, 18.3841) -> (34.5152, 28.8945) centre (36.4521, 22.6163) ccw projected
  line L1 (34.5152, 28.8945) -> (11.2616, 13.4908) projected
  arc A52 (6.5061, 12.4669) -> (11.2616, 13.4908) centre (7.7853, 18.0815) ccw projected
sketch "Szkic12" plane through (0, 0, 0) normal (0, 0, -1) x (-1, 0, 0)
  line L0 (34.5152, 28.8945) -> (11.2616, 13.4908) projected
  circle A0 centre (0, 0) radius 3 projected
  circle A1 centre (36.4521, 22.6163) radius 3 projected
  arc A2 (6.5061, 12.4669) -> (-14.0001, -1.3234) centre (0, 0) ccw projected
  arc A3 (-14.0001, -1.3234) -> (-16.6672, -2.6398) centre (-10.2643, -12.2524) ccw projected
  arc A4 (-16.6672, -2.6398) -> (-16.4686, -3.6812) centre (0, 0) ccw projected
  arc A5 (-16.4686, -3.6812) -> (-13.5041, -3.9233) centre (-14.0539, 7.6134) ccw projected
  arc A6 (-13.5041, -3.9233) -> (-13.2311, -4.7635) centre (0, 0) ccw projected
  arc A7 (-13.2311, -4.7635) -> (-15.4871, -6.7019) centre (-6.8948, -14.4201) ccw projected
  arc A8 (-15.4871, -6.7019) -> (-15.0357, -7.6611) centre (0, 0) ccw projected
  arc A9 (-15.0357, -7.6611) -> (-12.1042, -7.1584) centre (-15.5058, 3.8792) ccw projected
  arc A10 (-12.1042, -7.1584) -> (-11.6308, -7.9043) centre (0, 0) ccw projected
  arc A11 (-11.6308, -7.9043) -> (-13.3339, -10.3428) centre (-3.092, -15.6817) ccw projected
  arc A12 (-13.3339, -10.3428) -> (-12.6581, -11.1596) centre (0, 0) ccw projected
  arc A13 (-12.6581, -11.1596) -> (-9.9437, -9.9437) centre (-15.9833, -0.0988) ccw projected
  arc A14 (-9.9437, -9.9437) -> (-9.2997, -10.5484) centre (0, 0) ccw projected
  arc A15 (-9.2997, -10.5484) -> (-10.3428, -13.3339) centre (0.905, -15.958) ccw projected
  arc A16 (-10.3428, -13.3339) -> (-9.4852, -13.957) centre (0, 0) ccw projected
  arc A17 (-9.4852, -13.957) -> (-7.1584, -12.1042) centre (-15.4566, -4.0706) ccw projected
  arc A18 (-7.1584, -12.1042) -> (-6.3842, -12.5298) centre (0, 0) ccw projected
  arc A19 (-6.3842, -12.5298) -> (-6.7019, -15.4871) centre (4.8451, -15.2316) ccw projected
  arc A20 (-6.7019, -15.4871) -> (-5.7162, -15.8774) centre (0, 0) ccw projected
  arc A21 (-5.7162, -15.8774) -> (-3.9233, -13.5041) centre (-13.9587, -7.7866) ccw projected
  arc A22 (-3.9233, -13.5041) -> (-3.0676, -13.7238) centre (0, 0) ccw projected
  arc A23 (-3.0676, -13.7238) -> (-2.6398, -16.6672) centre (8.4809, -13.5481) ccw projected
  arc A24 (-2.6398, -16.6672) -> (-1.5881, -16.8001) centre (0, 0) ccw projected
  arc A25 (-1.5881, -16.8001) -> (-0.4417, -14.0556) centre (-11.5837, -11.0134) ccw projected
  arc A26 (-0.4417, -14.0556) -> (0.4417, -14.0556) centre (0, 0) ccw projected
  arc A27 (0.4417, -14.0556) -> (1.5881, -16.8001) centre (11.5837, -11.0134) ccw projected
  arc A28 (1.5881, -16.8001) -> (2.6398, -16.6672) centre (0, 0) ccw projected
  arc A29 (2.6398, -16.6672) -> (3.0676, -13.7238) centre (-8.4809, -13.5481) ccw projected
  arc A30 (3.0676, -13.7238) -> (3.9233, -13.5041) centre (0, 0) ccw projected
  arc A31 (3.9233, -13.5041) -> (5.7162, -15.8774) centre (13.9587, -7.7866) ccw projected
  arc A32 (5.7162, -15.8774) -> (6.7019, -15.4871) centre (0, 0) ccw projected
  arc A33 (6.7019, -15.4871) -> (6.3842, -12.5298) centre (-4.8451, -15.2316) ccw projected
  arc A34 (6.3842, -12.5298) -> (7.1584, -12.1042) centre (0, 0) ccw projected
  arc A35 (7.1584, -12.1042) -> (9.4852, -13.957) centre (15.4566, -4.0706) ccw projected
  arc A36 (9.4852, -13.957) -> (10.3428, -13.3339) centre (0, 0) ccw projected
  arc A37 (10.3428, -13.3339) -> (9.2997, -10.5484) centre (-0.905, -15.958) ccw projected
  arc A38 (9.2997, -10.5484) -> (9.9437, -9.9437) centre (0, 0) ccw projected
  arc A39 (9.9437, -9.9437) -> (12.6581, -11.1596) centre (15.9833, -0.0988) ccw projected
  arc A40 (12.6581, -11.1596) -> (13.3339, -10.3428) centre (0, 0) ccw projected
  arc A41 (13.3339, -10.3428) -> (11.6308, -7.9043) centre (3.092, -15.6817) ccw projected
  arc A42 (11.6308, -7.9043) -> (12.1042, -7.1584) centre (0, 0) ccw projected
  arc A43 (12.1042, -7.1584) -> (15.0357, -7.6611) centre (15.5058, 3.8792) ccw projected
  arc A44 (15.0357, -7.6611) -> (15.4871, -6.7019) centre (0, 0) ccw projected
  arc A45 (15.4871, -6.7019) -> (13.2311, -4.7635) centre (6.8948, -14.4201) ccw projected
  arc A46 (13.2311, -4.7635) -> (13.5041, -3.9233) centre (0, 0) ccw projected
  arc A47 (13.5041, -3.9233) -> (16.4686, -3.6812) centre (14.0539, 7.6134) ccw projected
  arc A48 (16.4686, -3.6812) -> (16.6672, -2.6398) centre (0, 0) ccw projected
  arc A49 (16.6672, -2.6398) -> (14.0001, -1.3234) centre (10.2643, -12.2524) ccw projected
  arc A50 (17.6188, 2.5795) -> (14.0001, -1.3234) centre (34.4614, -16.666) ccw projected
  line L1 (17.6188, 2.5795) -> (41.4775, 18.3841) projected
  arc A51 (41.4775, 18.3841) -> (34.5152, 28.8945) centre (36.4521, 22.6163) ccw projected
  line L2 (34.5152, 28.8945) -> (11.2616, 13.4908) projected
  arc A52 (6.5061, 12.4669) -> (11.2616, 13.4908) centre (7.7853, 18.0815) ccw projected
sketch "Szkic13" plane through (0, 0, 0) normal (0, 0, -1) x (-1, 0, 0)
  arc A0 (41.4775, 18.3841) -> (34.5152, 28.8945) centre (36.4521, 22.6163) ccw projected
  line L0 (34.5152, 28.8945) -> (11.2616, 13.4908) projected
  line L1 (29.1355, 25.3309) -> (36.0979, 14.8205)
  line L2 (41.4775, 18.3841) -> (17.6188, 2.5795) projected
  line L3 (17.6188, 2.5795) -> (41.4775, 18.3841) projected
  point P0 (0, 0)
  point P1 (41.9295, 26.2447)
  point P2 (41.9295, 26.2447)
  dimension "d61" = 49.4658
  dimension "d62" = 11.1707
  constraints: 2 end point, 2 point on circle, 2 point on line, 1 perpendicular
  measures "d61" distance of point (0, 0) point (41.929, 26.245)
  measures "d62" distance from line of point (41.929, 26.245) L1
extrude "Wyciągnięcie proste7" cut sketch "Szkic13" against normal blind 10
sketch "Szkic14" plane through (0, 0, 0) normal (0, 0, -1) x (-1, 0, 0)
  line L0 (36.0979, 14.8205) -> (29.1355, 25.3309) projected
  line L1 (29.1355, 25.3309) -> (11.2616, 13.4908) projected
  arc A0 (6.5061, 12.4669) -> (11.2616, 13.4908) centre (7.7853, 18.0815) ccw projected
  arc A1 (6.5061, 12.4669) -> (-14.0001, -1.3234) centre (0, 0) ccw projected
  arc A2 (-14.0001, -1.3234) -> (-16.6672, -2.6398) centre (-10.2643, -12.2524) ccw projected
  arc A3 (-16.6672, -2.6398) -> (-16.4686, -3.6812) centre (0, 0) ccw projected
  arc A4 (-16.4686, -3.6812) -> (-13.5041, -3.9233) centre (-14.0539, 7.6134) ccw projected
  arc A5 (-13.5041, -3.9233) -> (-13.2311, -4.7635) centre (0, 0) ccw projected
  arc A6 (-13.2311, -4.7635) -> (-15.4871, -6.7019) centre (-6.8948, -14.4201) ccw projected
  arc A7 (-15.4871, -6.7019) -> (-15.0357, -7.6611) centre (0, 0) ccw projected
  arc A8 (-15.0357, -7.6611) -> (-12.1042, -7.1584) centre (-15.5058, 3.8792) ccw projected
  arc A9 (-12.1042, -7.1584) -> (-11.6308, -7.9043) centre (0, 0) ccw projected
  arc A10 (-11.6308, -7.9043) -> (-13.3339, -10.3428) centre (-3.092, -15.6817) ccw projected
  arc A11 (-13.3339, -10.3428) -> (-12.6581, -11.1596) centre (0, 0) ccw projected
  arc A12 (-12.6581, -11.1596) -> (-9.9437, -9.9437) centre (-15.9833, -0.0988) ccw projected
  arc A13 (-9.9437, -9.9437) -> (-9.2997, -10.5484) centre (0, 0) ccw projected
  arc A14 (-9.2997, -10.5484) -> (-10.3428, -13.3339) centre (0.905, -15.958) ccw projected
  arc A15 (-10.3428, -13.3339) -> (-9.4852, -13.957) centre (0, 0) ccw projected
  arc A16 (-9.4852, -13.957) -> (-7.1584, -12.1042) centre (-15.4566, -4.0706) ccw projected
  arc A17 (-7.1584, -12.1042) -> (-6.3842, -12.5298) centre (0, 0) ccw projected
  arc A18 (-6.3842, -12.5298) -> (-6.7019, -15.4871) centre (4.8451, -15.2316) ccw projected
  arc A19 (-6.7019, -15.4871) -> (-5.7162, -15.8774) centre (0, 0) ccw projected
  arc A20 (-5.7162, -15.8774) -> (-3.9233, -13.5041) centre (-13.9587, -7.7866) ccw projected
  arc A21 (-3.9233, -13.5041) -> (-3.0676, -13.7238) centre (0, 0) ccw projected
  arc A22 (-3.0676, -13.7238) -> (-2.6398, -16.6672) centre (8.4809, -13.5481) ccw projected
  arc A23 (-2.6398, -16.6672) -> (-1.5881, -16.8001) centre (0, 0) ccw projected
  arc A24 (-1.5881, -16.8001) -> (-0.4417, -14.0556) centre (-11.5837, -11.0134) ccw projected
  arc A25 (-0.4417, -14.0556) -> (0.4417, -14.0556) centre (0, 0) ccw projected
  arc A26 (0.4417, -14.0556) -> (1.5881, -16.8001) centre (11.5837, -11.0134) ccw projected
  arc A27 (1.5881, -16.8001) -> (2.6398, -16.6672) centre (0, 0) ccw projected
  arc A28 (2.6398, -16.6672) -> (3.0676, -13.7238) centre (-8.4809, -13.5481) ccw projected
  arc A29 (3.0676, -13.7238) -> (3.9233, -13.5041) centre (0, 0) ccw projected
  arc A30 (3.9233, -13.5041) -> (5.7162, -15.8774) centre (13.9587, -7.7866) ccw projected
  arc A31 (5.7162, -15.8774) -> (6.7019, -15.4871) centre (0, 0) ccw projected
  arc A32 (6.7019, -15.4871) -> (6.3842, -12.5298) centre (-4.8451, -15.2316) ccw projected
  arc A33 (6.3842, -12.5298) -> (7.1584, -12.1042) centre (0, 0) ccw projected
  arc A34 (7.1584, -12.1042) -> (9.4852, -13.957) centre (15.4566, -4.0706) ccw projected
  arc A35 (9.4852, -13.957) -> (10.3428, -13.3339) centre (0, 0) ccw projected
  arc A36 (10.3428, -13.3339) -> (9.2997, -10.5484) centre (-0.905, -15.958) ccw projected
  arc A37 (9.2997, -10.5484) -> (9.9437, -9.9437) centre (0, 0) ccw projected
  arc A38 (9.9437, -9.9437) -> (12.6581, -11.1596) centre (15.9833, -0.0988) ccw projected
  arc A39 (12.6581, -11.1596) -> (13.3339, -10.3428) centre (0, 0) ccw projected
  arc A40 (13.3339, -10.3428) -> (11.6308, -7.9043) centre (3.092, -15.6817) ccw projected
  arc A41 (11.6308, -7.9043) -> (12.1042, -7.1584) centre (0, 0) ccw projected
  arc A42 (12.1042, -7.1584) -> (15.0357, -7.6611) centre (15.5058, 3.8792) ccw projected
  arc A43 (15.0357, -7.6611) -> (15.4871, -6.7019) centre (0, 0) ccw projected
  arc A44 (15.4871, -6.7019) -> (13.2311, -4.7635) centre (6.8948, -14.4201) ccw projected
  arc A45 (13.2311, -4.7635) -> (13.5041, -3.9233) centre (0, 0) ccw projected
  arc A46 (13.5041, -3.9233) -> (16.4686, -3.6812) centre (14.0539, 7.6134) ccw projected
  arc A47 (16.4686, -3.6812) -> (16.6672, -2.6398) centre (0, 0) ccw projected
  arc A48 (16.6672, -2.6398) -> (14.0001, -1.3234) centre (10.2643, -12.2524) ccw projected
  arc A49 (17.6188, 2.5795) -> (14.0001, -1.3234) centre (34.4614, -16.666) ccw projected
  line L2 (17.6188, 2.5795) -> (36.0979, 14.8205) projected
  circle A50 centre (0, 0) radius 3 projected
  line L3 (29.1355, 25.3309) -> (36.0979, 14.8205)
  line L4 (36.0979, 14.8205) -> (43.0908, 19.4527)
  line L5 (43.0908, 19.4527) -> (36.1284, 29.9632)
  line L6 (36.1284, 29.9632) -> (29.1355, 25.3309)
  arc A51 (43.0908, 19.4527) -> (36.1284, 29.9632) centre (38.1214, 23.7222) ccw
  circle A52 centre (38.1214, 23.7222) radius 3.0005
  point P0 (41.4945, 18.3953)
  dimension "d65" = 8.388
  constraints: 8 end point, 3 equal length, 2 centre point, 2 point on circle, 1 coincident, 1 perpendicular, 1 point on line
  measures "d65" distance of L0.start L4.end
extrude "Wyciągnięcie proste8" add sketch "Szkic14" against normal blind 5 contours L0 L6 L5 A52 L4 | L5 A52 A51
sketch "Szkic15" plane through (0, 0, 5) normal (0, 0, 1) x (1, 0, 0)
  circle A0 centre (0, 0) radius 2
  circle A1 centre (-38.1214, 23.7222) radius 3.0005 projected
  circle A2 centre (-38.1214, 23.7222) radius 2
  dimension "d68" = 4
  dimension "d69" = 4
  constraints: 2 centre point, 2 coincident
  measures "d68" diameter of A2
  measures "d69" diameter of A0
extrude "Wyciągnięcie proste9" add sketch "Szkic15" against normal blind 5 contours A1
sketch "Szkic16" plane through (0, 0, 5) normal (0, 0, 1) x (1, 0, 0)
  circle A0 centre (0, 0) radius 3 projected
  circle A1 centre (0, 0) radius 2
  dimension "d72" = 4
  constraints: 1 centre point, 1 coincident
  measures "d72" diameter of A1
extrude "Wyciągnięcie proste10" add sketch "Szkic16" against normal blind 5
sketch "Szkic17" plane through (0, 0, 0) normal (0, 0, -1) x (-1, 0, 0)
  point P0 (0, 0)
sketch "Szkic18" plane through (0, 0, 5) normal (0, 0, 1) x (1, 0, 0)
  circle A0 centre (-9.2806, 4.407) radius 52.2718
  point P0 (0, 0)
  constraints: 1 centre point
extrude "Wyciągnięcie proste11" cut sketch "Szkic18" against normal blind 0.5
equation "\"d0\" = da_da"
equation "\"d1\" = da_b"
equation "\"d3\" = da_d"
equation "\"d16\" = da_aw"
equation "\"d43\" = da_aw"
equation "\"d46\" = da_aw"
equation "\"da_da\" = 33.75"
equation "\"da_b\" = 10"
equation "\"da_d\" = 31.25"
equation "\"da_aw\" = 109.375"
body "Solid1"
body "Srf1"
